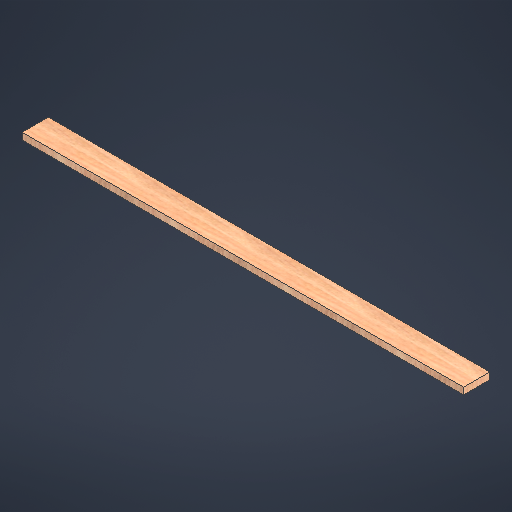
# Autodesk Inventor part: Pilar_sin_cortar_v0
Saved by Autodesk Inventor 2027 (Build 310192060, 192F)
## iProperties
Created: 2026-10-11
Part Number: Pilar_sin_cortar_v0
Material: Generic
Document SubType Name: Modeling
Designer: Pablo
Density: 1 g/cm^3
Appearance: Default
Author: Pablo
Autodesk Inventor part; units mm, degrees
ref_plane "YZ Plane" through (0, 0, 0) normal (1, 0, 0) x (0, 1, 0)
ref_plane "XZ Plane" through (0, 0, 0) normal (0, 1, 0) x (-1, 0, 0)
ref_plane "XY Plane" through (0, 0, 0) normal (0, 0, 1) x (1, 0, 0)
sketch "Sketch1" plane through (0, 0, 0) normal (0, 1, 0) x (-1, 0, 0)
  line L0 (-495, 29.5) -> (495, 29.5)
  line L1 (495, 29.5) -> (495, -29.5)
  line L2 (495, -29.5) -> (-495, -29.5)
  line L3 (-495, -29.5) -> (-495, 29.5)
  line L4 (-495, 29.5) -> (495, -29.5) construction
  line L5 (495, 29.5) -> (-495, -29.5) construction
  point P0 (0, 0)
  dimension "d0" = 990
  dimension "d1" = 59
  constraints: 12 end point, 2 midpoint, 2 parallel, 1 horizontal, 1 perpendicular
  measures "d0" distance of L1.end L2.end
  measures "d1" distance of L0.end L1.end
extrude "Extrusion1" add sketch "Sketch1" along normal blind 15
body "Solid1"
